Autodesk Fusion 360 part; units mm, degrees
(part 3 of 4)
extrude "Front seam M3x6 clearance (1)" cut sketch "草图15 (4)" along normal blind 3.01 contours A0 in plane through (0, -13, 0) normal (0, 1, 0) bodies 25 in component "12_front_CPU_SUPPORT_FRAME"
ref_plane "工作平面14" through (0, 10, 0) normal (0, 1, 0) x (0, 0, 1) in component "12_front_PCI_SUPPORT_FRAME"
sketch "草图14 (5)" plane through (0, 10, 0) normal (0, 1, 0) x (1, 0, 0) in component "12_front_PCI_SUPPORT_FRAME"
  circle A0 through (148.35, -132, -20) (144.825, -129.9648, -20) (144.825, -134.0352, -20)
extrude "Front seam H4.5 insert (1)" cut sketch "草图14 (5)" along normal blind 6.5 contours A0 in plane through (0, -10, 0) normal (0, 1, 0) bodies 24 in component "12_front_PCI_SUPPORT_FRAME"
ref_plane "工作平面6" through (0, 0, 0) normal (0, 0, 1) x (1, 0, 0) in component "04_front_GROUND_BAR_290mm_FLAT_PSU"
sketch "草图6 (16)" plane through (0, 0, 0) normal (0, 0, 1) x (1, 0, 0) in component "04_front_GROUND_BAR_290mm_FLAT_PSU"
  line L0 (20.45, 29.92) -> (28.45, 29.92)
  line L1 (28.45, 29.92) -> (28.45, 49.92)
  line L2 (28.45, 49.92) -> (20.45, 49.92)
  line L3 (20.45, 49.92) -> (20.45, 29.92)
extrude "PCI bottom lap end seat" add sketch "草图6 (16)" along normal blind 3.2 bodies 18 in component "04_front_GROUND_BAR_290mm_FLAT_PSU"
ref_plane "工作平面7" through (0, 0, 0) normal (0, 0, 1) x (1, 0, 0) in component "04_front_GROUND_BAR_290mm_FLAT_PSU"
sketch "草图7 (14)" plane through (0, 0, 0) normal (0, 0, 1) x (1, 0, 0) in component "04_front_GROUND_BAR_290mm_FLAT_PSU"
  line L0 (286.45, 29.92) -> (294.45, 29.92)
  line L1 (294.45, 29.92) -> (294.45, 49.92)
  line L2 (294.45, 49.92) -> (286.45, 49.92)
  line L3 (286.45, 49.92) -> (286.45, 29.92)
extrude "CPU bottom lap end seat" add sketch "草图7 (14)" along normal blind 3.2 bodies 18 in component "04_front_GROUND_BAR_290mm_FLAT_PSU"
ref_plane "工作平面11" through (0, 0, -0.01) normal (0, 0, 1) x (1, 0, 0) in component "16_PCI_INSET_SIDE_16_45mm"
sketch "草图11 (9)" plane through (0, 0, -0.01) normal (0, 0, 1) x (1, 0, 0) in component "16_PCI_INSET_SIDE_16_45mm"
  line L0 (20.3, 29.77) -> (28.6, 29.77)
  line L1 (28.6, 29.77) -> (28.6, 50.07)
  line L2 (28.6, 50.07) -> (20.3, 50.07)
  line L3 (20.3, 50.07) -> (20.3, 29.77)
extrude "Ground bar seat with lateral print clearance" cut sketch "草图11 (9)" along normal blind 3.21 bodies 27 in component "16_PCI_INSET_SIDE_16_45mm"
ref_plane "工作平面8" through (0, 0, 0) normal (0, 0, 1) x (1, 0, 0) in component "04_front_GROUND_BAR_290mm_FLAT_PSU"
sketch "草图8 (14)" plane through (0, 0, 0) normal (0, 0, 1) x (1, 0, 0) in component "04_front_GROUND_BAR_290mm_FLAT_PSU"
  circle A0 centre (24.45, 39.92) radius 1.7
extrude "Bottom lap M3x6 clearance" cut sketch "草图8 (14)" along normal blind 3.21 bodies 18 in component "04_front_GROUND_BAR_290mm_FLAT_PSU"
ref_plane "工作平面12" through (0, 0, 3.2) normal (0, 0, 1) x (1, 0, 0) in component "16_PCI_INSET_SIDE_16_45mm"
sketch "草图12 (7)" plane through (0, 0, 3.2) normal (0, 0, 1) x (1, 0, 0) in component "16_PCI_INSET_SIDE_16_45mm"
  circle A0 centre (24.45, 39.92) radius 2.35
extrude "Bottom entry H4.5 insert for floor tie" cut sketch "草图12 (7)" along normal blind 6.5 bodies 27 in component "16_PCI_INSET_SIDE_16_45mm"
ref_plane "工作平面9" through (0, 0, -0.01) normal (0, 0, 1) x (1, 0, 0) in component "16_CPU_VERTICAL_SIDE_FLUSH_TO_BEAM"
sketch "草图9 (13)" plane through (0, 0, -0.01) normal (0, 0, 1) x (1, 0, 0) in component "16_CPU_VERTICAL_SIDE_FLUSH_TO_BEAM"
  line L0 (286.3, 29.77) -> (294.6, 29.77)
  line L1 (294.6, 29.77) -> (294.6, 50.07)
  line L2 (294.6, 50.07) -> (286.3, 50.07)
  line L3 (286.3, 50.07) -> (286.3, 29.77)
extrude "Ground bar seat with lateral print clearance'" cut sketch "草图9 (13)" along normal blind 3.21 bodies 26 in component "16_CPU_VERTICAL_SIDE_FLUSH_TO_BEAM"
ref_plane "工作平面9" through (0, 0, 0) normal (0, 0, 1) x (1, 0, 0) in component "04_front_GROUND_BAR_290mm_FLAT_PSU"
sketch "草图9 (14)" plane through (0, 0, 0) normal (0, 0, 1) x (1, 0, 0) in component "04_front_GROUND_BAR_290mm_FLAT_PSU"
  circle A0 centre (290.45, 39.92) radius 1.7
extrude "Bottom lap M3x6 clearance (1)" cut sketch "草图9 (14)" along normal blind 3.21 bodies 18 in component "04_front_GROUND_BAR_290mm_FLAT_PSU"
ref_plane "工作平面10" through (0, 0, 3.2) normal (0, 0, 1) x (1, 0, 0) in component "16_CPU_VERTICAL_SIDE_FLUSH_TO_BEAM"
sketch "草图10 (11)" plane through (0, 0, 3.2) normal (0, 0, 1) x (1, 0, 0) in component "16_CPU_VERTICAL_SIDE_FLUSH_TO_BEAM"
  circle A0 centre (290.45, 39.92) radius 2.35
extrude "Bottom entry H4.5 insert for floor tie'" cut sketch "草图10 (11)" along normal blind 6.5 bodies 26 in component "16_CPU_VERTICAL_SIDE_FLUSH_TO_BEAM"
ref_plane "工作平面17" through (0, 0, 8) normal (0, 0, 1) x (1, 0, 0) in component "05_CENTERED_FLAT_PSU_CRADLE_OPEN_INTAKE"
sketch "草图17" plane through (0, 0, 8) normal (0, 0, 1) x (1, 0, 0) in component "05_CENTERED_FLAT_PSU_CRADLE_OPEN_INTAKE"
  circle A0 centre (79.4, 39.92) radius 1.7
extrude "Cradle to crossbar screw clearance" cut sketch "草图17" along normal blind 22.01 bodies 20 in component "05_CENTERED_FLAT_PSU_CRADLE_OPEN_INTAKE"
ref_plane "工作平面18" through (0, 0, 11) normal (0, 0, 1) x (1, 0, 0) in component "05_CENTERED_FLAT_PSU_CRADLE_OPEN_INTAKE"
sketch "草图18" plane through (0, 0, 11) normal (0, 0, 1) x (1, 0, 0) in component "05_CENTERED_FLAT_PSU_CRADLE_OPEN_INTAKE"
  circle A0 centre (79.4, 39.92) radius 3.3
extrude "Cradle screw well leaving 3 mm web" cut sketch "草图18" along normal blind 19.01 bodies 20 in component "05_CENTERED_FLAT_PSU_CRADLE_OPEN_INTAKE"
ref_plane "工作平面10" through (0, 0, 1.5) normal (0, 0, 1) x (1, 0, 0) in component "04_front_GROUND_BAR_290mm_FLAT_PSU"
sketch "草图10 (12)" plane through (0, 0, 1.5) normal (0, 0, 1) x (1, 0, 0) in component "04_front_GROUND_BAR_290mm_FLAT_PSU"
  circle A0 centre (79.4, 39.92) radius 2.35
extrude "Top entry H4.5 insert for cradle foot" cut sketch "草图10 (12)" along normal blind 6.51 bodies 18 in component "04_front_GROUND_BAR_290mm_FLAT_PSU"
ref_plane "工作平面19" through (0, 0, 8) normal (0, 0, 1) x (1, 0, 0) in component "05_CENTERED_FLAT_PSU_CRADLE_OPEN_INTAKE"
sketch "草图19" plane through (0, 0, 8) normal (0, 0, 1) x (1, 0, 0) in component "05_CENTERED_FLAT_PSU_CRADLE_OPEN_INTAKE"
  circle A0 centre (225.4, 39.92) radius 1.7
extrude "Cradle to crossbar screw clearance (1)" cut sketch "草图19" along normal blind 22.01 bodies 20 in component "05_CENTERED_FLAT_PSU_CRADLE_OPEN_INTAKE"
ref_plane "工作平面20" through (0, 0, 11) normal (0, 0, 1) x (1, 0, 0) in component "05_CENTERED_FLAT_PSU_CRADLE_OPEN_INTAKE"
sketch "草图20" plane through (0, 0, 11) normal (0, 0, 1) x (1, 0, 0) in component "05_CENTERED_FLAT_PSU_CRADLE_OPEN_INTAKE"
  circle A0 centre (225.4, 39.92) radius 3.3
extrude "Cradle screw well leaving 3 mm web (1)" cut sketch "草图20" along normal blind 19.01 bodies 20 in component "05_CENTERED_FLAT_PSU_CRADLE_OPEN_INTAKE"
ref_plane "工作平面11" through (0, 0, 1.5) normal (0, 0, 1) x (1, 0, 0) in component "04_front_GROUND_BAR_290mm_FLAT_PSU"
sketch "草图11 (10)" plane through (0, 0, 1.5) normal (0, 0, 1) x (1, 0, 0) in component "04_front_GROUND_BAR_290mm_FLAT_PSU"
  circle A0 centre (225.4, 39.92) radius 2.35
extrude "Top entry H4.5 insert for cradle foot (1)" cut sketch "草图11 (10)" along normal blind 6.51 bodies 18 in component "04_front_GROUND_BAR_290mm_FLAT_PSU"
ref_plane "工作平面6" through (0, 0, 0) normal (0, 0, 1) x (1, 0, 0) in component "04_rear_GROUND_BAR_290mm_FLAT_PSU"
sketch "草图6 (17)" plane through (0, 0, 0) normal (0, 0, 1) x (1, 0, 0) in component "04_rear_GROUND_BAR_290mm_FLAT_PSU"
  line L0 (20.45, 193.92) -> (28.45, 193.92)
  line L1 (28.45, 193.92) -> (28.45, 213.92)
  line L2 (28.45, 213.92) -> (20.45, 213.92)
  line L3 (20.45, 213.92) -> (20.45, 193.92)
extrude "PCI bottom lap end seat'" add sketch "草图6 (17)" along normal blind 3.2 bodies 19 in component "04_rear_GROUND_BAR_290mm_FLAT_PSU"
ref_plane "工作平面7" through (0, 0, 0) normal (0, 0, 1) x (1, 0, 0) in component "04_rear_GROUND_BAR_290mm_FLAT_PSU"
sketch "草图7 (15)" plane through (0, 0, 0) normal (0, 0, 1) x (1, 0, 0) in component "04_rear_GROUND_BAR_290mm_FLAT_PSU"
  line L0 (286.45, 193.92) -> (294.45, 193.92)
  line L1 (294.45, 193.92) -> (294.45, 213.92)
  line L2 (294.45, 213.92) -> (286.45, 213.92)
  line L3 (286.45, 213.92) -> (286.45, 193.92)
extrude "CPU bottom lap end seat'" add sketch "草图7 (15)" along normal blind 3.2 bodies 19 in component "04_rear_GROUND_BAR_290mm_FLAT_PSU"
ref_plane "工作平面13" through (0, 0, -0.01) normal (0, 0, 1) x (1, 0, 0) in component "16_PCI_INSET_SIDE_16_45mm"
sketch "草图13 (7)" plane through (0, 0, -0.01) normal (0, 0, 1) x (1, 0, 0) in component "16_PCI_INSET_SIDE_16_45mm"
  line L0 (20.3, 193.77) -> (28.6, 193.77)
  line L1 (28.6, 193.77) -> (28.6, 214.07)
  line L2 (28.6, 214.07) -> (20.3, 214.07)
  line L3 (20.3, 214.07) -> (20.3, 193.77)
extrude "Ground bar seat with lateral print clearance (1)" cut sketch "草图13 (7)" along normal blind 3.21 bodies 27 in component "16_PCI_INSET_SIDE_16_45mm"
ref_plane "工作平面8" through (0, 0, 0) normal (0, 0, 1) x (1, 0, 0) in component "04_rear_GROUND_BAR_290mm_FLAT_PSU"
sketch "草图8 (15)" plane through (0, 0, 0) normal (0, 0, 1) x (1, 0, 0) in component "04_rear_GROUND_BAR_290mm_FLAT_PSU"
  circle A0 centre (24.45, 203.92) radius 1.7
extrude "Bottom lap M3x6 clearance'" cut sketch "草图8 (15)" along normal blind 3.21 bodies 19 in component "04_rear_GROUND_BAR_290mm_FLAT_PSU"
ref_plane "工作平面14" through (0, 0, 3.2) normal (0, 0, 1) x (1, 0, 0) in component "16_PCI_INSET_SIDE_16_45mm"
sketch "草图14 (6)" plane through (0, 0, 3.2) normal (0, 0, 1) x (1, 0, 0) in component "16_PCI_INSET_SIDE_16_45mm"
  circle A0 centre (24.45, 203.92) radius 2.35
extrude "Bottom entry H4.5 insert for floor tie (1)" cut sketch "草图14 (6)" along normal blind 6.5 bodies 27 in component "16_PCI_INSET_SIDE_16_45mm"
ref_plane "工作平面11" through (0, 0, -0.01) normal (0, 0, 1) x (1, 0, 0) in component "16_CPU_VERTICAL_SIDE_FLUSH_TO_BEAM"
sketch "草图11 (11)" plane through (0, 0, -0.01) normal (0, 0, 1) x (1, 0, 0) in component "16_CPU_VERTICAL_SIDE_FLUSH_TO_BEAM"
  line L0 (286.3, 193.77) -> (294.6, 193.77)
  line L1 (294.6, 193.77) -> (294.6, 214.07)
  line L2 (294.6, 214.07) -> (286.3, 214.07)
  line L3 (286.3, 214.07) -> (286.3, 193.77)
extrude "Ground bar seat with lateral print clearance (1)'" cut sketch "草图11 (11)" along normal blind 3.21 bodies 26 in component "16_CPU_VERTICAL_SIDE_FLUSH_TO_BEAM"
ref_plane "工作平面9" through (0, 0, 0) normal (0, 0, 1) x (1, 0, 0) in component "04_rear_GROUND_BAR_290mm_FLAT_PSU"
sketch "草图9 (15)" plane through (0, 0, 0) normal (0, 0, 1) x (1, 0, 0) in component "04_rear_GROUND_BAR_290mm_FLAT_PSU"
  circle A0 centre (290.45, 203.92) radius 1.7
extrude "Bottom lap M3x6 clearance (1)'" cut sketch "草图9 (15)" along normal blind 3.21 bodies 19 in component "04_rear_GROUND_BAR_290mm_FLAT_PSU"
ref_plane "工作平面12" through (0, 0, 3.2) normal (0, 0, 1) x (1, 0, 0) in component "16_CPU_VERTICAL_SIDE_FLUSH_TO_BEAM"
sketch "草图12 (8)" plane through (0, 0, 3.2) normal (0, 0, 1) x (1, 0, 0) in component "16_CPU_VERTICAL_SIDE_FLUSH_TO_BEAM"
  circle A0 centre (290.45, 203.92) radius 2.35
extrude "Bottom entry H4.5 insert for floor tie (1)'" cut sketch "草图12 (8)" along normal blind 6.5 bodies 26 in component "16_CPU_VERTICAL_SIDE_FLUSH_TO_BEAM"
ref_plane "工作平面21" through (0, 0, 8) normal (0, 0, 1) x (1, 0, 0) in component "05_CENTERED_FLAT_PSU_CRADLE_OPEN_INTAKE"
sketch "草图21" plane through (0, 0, 8) normal (0, 0, 1) x (1, 0, 0) in component "05_CENTERED_FLAT_PSU_CRADLE_OPEN_INTAKE"
  circle A0 centre (79.4, 203.92) radius 1.7
extrude "Cradle to crossbar screw clearance (2)" cut sketch "草图21" along normal blind 22.01 bodies 20 in component "05_CENTERED_FLAT_PSU_CRADLE_OPEN_INTAKE"
ref_plane "工作平面22" through (0, 0, 11) normal (0, 0, 1) x (1, 0, 0) in component "05_CENTERED_FLAT_PSU_CRADLE_OPEN_INTAKE"
sketch "草图22" plane through (0, 0, 11) normal (0, 0, 1) x (1, 0, 0) in component "05_CENTERED_FLAT_PSU_CRADLE_OPEN_INTAKE"
  circle A0 centre (79.4, 203.92) radius 3.3
extrude "Cradle screw well leaving 3 mm web (2)" cut sketch "草图22" along normal blind 19.01 bodies 20 in component "05_CENTERED_FLAT_PSU_CRADLE_OPEN_INTAKE"
ref_plane "工作平面10" through (0, 0, 1.5) normal (0, 0, 1) x (1, 0, 0) in component "04_rear_GROUND_BAR_290mm_FLAT_PSU"
sketch "草图10 (13)" plane through (0, 0, 1.5) normal (0, 0, 1) x (1, 0, 0) in component "04_rear_GROUND_BAR_290mm_FLAT_PSU"
  circle A0 centre (79.4, 203.92) radius 2.35
extrude "Top entry H4.5 insert for cradle foot'" cut sketch "草图10 (13)" along normal blind 6.51 bodies 19 in component "04_rear_GROUND_BAR_290mm_FLAT_PSU"
ref_plane "工作平面23" through (0, 0, 8) normal (0, 0, 1) x (1, 0, 0) in component "05_CENTERED_FLAT_PSU_CRADLE_OPEN_INTAKE"
sketch "草图23" plane through (0, 0, 8) normal (0, 0, 1) x (1, 0, 0) in component "05_CENTERED_FLAT_PSU_CRADLE_OPEN_INTAKE"
  circle A0 centre (225.4, 203.92) radius 1.7
extrude "Cradle to crossbar screw clearance (3)" cut sketch "草图23" along normal blind 22.01 bodies 20 in component "05_CENTERED_FLAT_PSU_CRADLE_OPEN_INTAKE"
ref_plane "工作平面24" through (0, 0, 11) normal (0, 0, 1) x (1, 0, 0) in component "05_CENTERED_FLAT_PSU_CRADLE_OPEN_INTAKE"
sketch "草图24" plane through (0, 0, 11) normal (0, 0, 1) x (1, 0, 0) in component "05_CENTERED_FLAT_PSU_CRADLE_OPEN_INTAKE"
  circle A0 centre (225.4, 203.92) radius 3.3
extrude "Cradle screw well leaving 3 mm web (3)" cut sketch "草图24" along normal blind 19.01 bodies 20 in component "05_CENTERED_FLAT_PSU_CRADLE_OPEN_INTAKE"
ref_plane "工作平面11" through (0, 0, 1.5) normal (0, 0, 1) x (1, 0, 0) in component "04_rear_GROUND_BAR_290mm_FLAT_PSU"
sketch "草图11 (12)" plane through (0, 0, 1.5) normal (0, 0, 1) x (1, 0, 0) in component "04_rear_GROUND_BAR_290mm_FLAT_PSU"
  circle A0 centre (225.4, 203.92) radius 2.35
extrude "Top entry H4.5 insert for cradle foot (1)'" cut sketch "草图11 (12)" along normal blind 6.51 bodies 19 in component "04_rear_GROUND_BAR_290mm_FLAT_PSU"
ref_plane "工作平面25" through (0, 0, 23.99) normal (0, 0, 1) x (1, 0, 0) in component "05_CENTERED_FLAT_PSU_CRADLE_OPEN_INTAKE"
sketch "草图25" plane through (0, 0, 23.99) normal (0, 0, 1) x (1, 0, 0) in component "05_CENTERED_FLAT_PSU_CRADLE_OPEN_INTAKE"
  line L0 (87.1, 35) -> (90.7, 35)
  line L1 (90.7, 35) -> (90.7, 37.4)
  line L2 (90.7, 37.4) -> (87.1, 37.4)
  line L3 (87.1, 37.4) -> (87.1, 35)
extrude "3 mm strap slot outside PSU fan intake" cut sketch "草图25" along normal blind 6.02 bodies 20 in component "05_CENTERED_FLAT_PSU_CRADLE_OPEN_INTAKE"
ref_plane "工作平面26" through (0, 0, 23.99) normal (0, 0, 1) x (1, 0, 0) in component "05_CENTERED_FLAT_PSU_CRADLE_OPEN_INTAKE"
sketch "草图26" plane through (0, 0, 23.99) normal (0, 0, 1) x (1, 0, 0) in component "05_CENTERED_FLAT_PSU_CRADLE_OPEN_INTAKE"
  line L0 (87.1, 206.2) -> (90.7, 206.2)
  line L1 (90.7, 206.2) -> (90.7, 208.6)
  line L2 (90.7, 208.6) -> (87.1, 208.6)
  line L3 (87.1, 208.6) -> (87.1, 206.2)
extrude "3 mm strap slot outside PSU fan intake (1)" cut sketch "草图26" along normal blind 6.02 bodies 20 in component "05_CENTERED_FLAT_PSU_CRADLE_OPEN_INTAKE"
ref_plane "工作平面27" through (0, 0, 23.99) normal (0, 0, 1) x (1, 0, 0) in component "05_CENTERED_FLAT_PSU_CRADLE_OPEN_INTAKE"
sketch "草图27" plane through (0, 0, 23.99) normal (0, 0, 1) x (1, 0, 0) in component "05_CENTERED_FLAT_PSU_CRADLE_OPEN_INTAKE"
  line L0 (214.1, 35) -> (217.7, 35)
  line L1 (217.7, 35) -> (217.7, 37.4)
  line L2 (217.7, 37.4) -> (214.1, 37.4)
  line L3 (214.1, 37.4) -> (214.1, 35)
extrude "3 mm strap slot outside PSU fan intake (2)" cut sketch "草图27" along normal blind 6.02 bodies 20 in component "05_CENTERED_FLAT_PSU_CRADLE_OPEN_INTAKE"
ref_plane "工作平面28" through (0, 0, 23.99) normal (0, 0, 1) x (1, 0, 0) in component "05_CENTERED_FLAT_PSU_CRADLE_OPEN_INTAKE"
sketch "草图28" plane through (0, 0, 23.99) normal (0, 0, 1) x (1, 0, 0) in component "05_CENTERED_FLAT_PSU_CRADLE_OPEN_INTAKE"
  line L0 (214.1, 206.2) -> (217.7, 206.2)
  line L1 (217.7, 206.2) -> (217.7, 208.6)
  line L2 (217.7, 208.6) -> (214.1, 208.6)
  line L3 (214.1, 208.6) -> (214.1, 206.2)
extrude "3 mm strap slot outside PSU fan intake (3)" cut sketch "草图28" along normal blind 6.02 bodies 20 in component "05_CENTERED_FLAT_PSU_CRADLE_OPEN_INTAKE"
ref_plane "工作平面7" through (0, 0, 210) normal (0, 0, 1) x (1, 0, 0) in component "10_GPU_140_FAN_MOUNT"
sketch "草图7 (16)" plane through (0, 0, 210) normal (0, 0, 1) x (1, 0, 0) in component "10_GPU_140_FAN_MOUNT"
  line L0 (26.4, -19) -> (38.4, -19)
  line L1 (38.4, -19) -> (38.4, -9)
  line L2 (38.4, -9) -> (26.4, -9)
  line L3 (26.4, -9) -> (26.4, -19)
extrude "Integral 3 mm fan panel fastening tab" add sketch "草图7 (16)" along normal blind 3 bodies 1 in component "10_GPU_140_FAN_MOUNT"
ref_plane "工作平面8" through (0, 0, 210) normal (0, 0, 1) x (1, 0, 0) in component "10_GPU_140_FAN_MOUNT"
sketch "草图8 (16)" plane through (0, 0, 210) normal (0, 0, 1) x (1, 0, 0) in component "10_GPU_140_FAN_MOUNT"
  circle A0 centre (32.4, -14) radius 1.7
extrude "M3x6 fan panel tab clearance" cut sketch "草图8 (16)" along normal blind 3.01 bodies 1 in component "10_GPU_140_FAN_MOUNT"
ref_plane "工作平面14" through (0, 0, 148) normal (0, 0, 1) x (1, 0, 0) in component "20_ONE_PIECE_DUAL_140_FAN_RAIL_284mm"
sketch "草图14 (7)" plane through (0, 0, 148) normal (0, 0, 1) x (1, 0, 0) in component "20_ONE_PIECE_DUAL_140_FAN_RAIL_284mm"
  line L0 (26.4, -19) -> (38.4, -19)
  line L1 (38.4, -19) -> (38.4, -9)
  line L2 (38.4, -9) -> (26.4, -9)
  line L3 (26.4, -9) -> (26.4, -19)
extrude "Integral fan panel tab support pad" add sketch "草图14 (7)" along normal blind 12 bodies 32 in component "20_ONE_PIECE_DUAL_140_FAN_RAIL_284mm"
ref_plane "工作平面15" through (0, 0, 153.5) normal (0, 0, 1) x (1, 0, 0) in component "20_ONE_PIECE_DUAL_140_FAN_RAIL_284mm"
sketch "草图15 (5)" plane through (0, 0, 153.5) normal (0, 0, 1) x (1, 0, 0) in component "20_ONE_PIECE_DUAL_140_FAN_RAIL_284mm"
  circle A0 centre (32.4, -14) radius 2.35
extrude "H4.5 insert for fan panel M3x6 fastening" cut sketch "草图15 (5)" along normal blind 6.51 bodies 32 in component "20_ONE_PIECE_DUAL_140_FAN_RAIL_284mm"
ref_plane "工作平面9" through (0, 0, 210) normal (0, 0, 1) x (1, 0, 0) in component "10_GPU_140_FAN_MOUNT"
sketch "草图9 (16)" plane through (0, 0, 210) normal (0, 0, 1) x (1, 0, 0) in component "10_GPU_140_FAN_MOUNT"
  line L0 (126.4, -19) -> (138.4, -19)
  line L1 (138.4, -19) -> (138.4, -9)
  line L2 (138.4, -9) -> (126.4, -9)
  line L3 (126.4, -9) -> (126.4, -19)
extrude "Integral 3 mm fan panel fastening tab (1)" add sketch "草图9 (16)" along normal blind 3 bodies 1 in component "10_GPU_140_FAN_MOUNT"
ref_plane "工作平面10" through (0, 0, 210) normal (0, 0, 1) x (1, 0, 0) in component "10_GPU_140_FAN_MOUNT"
sketch "草图10 (14)" plane through (0, 0, 210) normal (0, 0, 1) x (1, 0, 0) in component "10_GPU_140_FAN_MOUNT"
  circle A0 centre (132.4, -14) radius 1.7
extrude "M3x6 fan panel tab clearance (1)" cut sketch "草图10 (14)" along normal blind 3.01 bodies 1 in component "10_GPU_140_FAN_MOUNT"
ref_plane "工作平面16" through (0, 0, 148) normal (0, 0, 1) x (1, 0, 0) in component "20_ONE_PIECE_DUAL_140_FAN_RAIL_284mm"
sketch "草图16 (4)" plane through (0, 0, 148) normal (0, 0, 1) x (1, 0, 0) in component "20_ONE_PIECE_DUAL_140_FAN_RAIL_284mm"
  line L0 (126.4, -19) -> (138.4, -19)
  line L1 (138.4, -19) -> (138.4, -9)
  line L2 (138.4, -9) -> (126.4, -9)
  line L3 (126.4, -9) -> (126.4, -19)
extrude "Integral fan panel tab support pad (1)" add sketch "草图16 (4)" along normal blind 12 bodies 32 in component "20_ONE_PIECE_DUAL_140_FAN_RAIL_284mm"
ref_plane "工作平面17" through (0, 0, 153.5) normal (0, 0, 1) x (1, 0, 0) in component "20_ONE_PIECE_DUAL_140_FAN_RAIL_284mm"
sketch "草图17 (2)" plane through (0, 0, 153.5) normal (0, 0, 1) x (1, 0, 0) in component "20_ONE_PIECE_DUAL_140_FAN_RAIL_284mm"
  circle A0 centre (132.4, -14) radius 2.35
extrude "H4.5 insert for fan panel M3x6 fastening (1)" cut sketch "草图17 (2)" along normal blind 6.51 bodies 32 in component "20_ONE_PIECE_DUAL_140_FAN_RAIL_284mm"
ref_plane "工作平面7" through (0, 0, 210) normal (0, 0, 1) x (1, 0, 0) in component "10_CPU_140_FAN_MOUNT"
sketch "草图7 (17)" plane through (0, 0, 210) normal (0, 0, 1) x (1, 0, 0) in component "10_CPU_140_FAN_MOUNT"
  line L0 (170.4, -19) -> (182.4, -19)
  line L1 (182.4, -19) -> (182.4, -9)
  line L2 (182.4, -9) -> (170.4, -9)
  line L3 (170.4, -9) -> (170.4, -19)
extrude "Integral 3 mm fan panel fastening tab'" add sketch "草图7 (17)" along normal blind 3 bodies 2 in component "10_CPU_140_FAN_MOUNT"
ref_plane "工作平面8" through (0, 0, 210) normal (0, 0, 1) x (1, 0, 0) in component "10_CPU_140_FAN_MOUNT"
sketch "草图8 (17)" plane through (0, 0, 210) normal (0, 0, 1) x (1, 0, 0) in component "10_CPU_140_FAN_MOUNT"
  circle A0 centre (176.4, -14) radius 1.7
extrude "M3x6 fan panel tab clearance'" cut sketch "草图8 (17)" along normal blind 3.01 bodies 2 in component "10_CPU_140_FAN_MOUNT"
ref_plane "工作平面18" through (0, 0, 148) normal (0, 0, 1) x (1, 0, 0) in component "20_ONE_PIECE_DUAL_140_FAN_RAIL_284mm"
sketch "草图18 (2)" plane through (0, 0, 148) normal (0, 0, 1) x (1, 0, 0) in component "20_ONE_PIECE_DUAL_140_FAN_RAIL_284mm"
  line L0 (170.4, -19) -> (182.4, -19)
  line L1 (182.4, -19) -> (182.4, -9)
  line L2 (182.4, -9) -> (170.4, -9)
  line L3 (170.4, -9) -> (170.4, -19)
extrude "Integral fan panel tab support pad (2)" add sketch "草图18 (2)" along normal blind 12 bodies 32 in component "20_ONE_PIECE_DUAL_140_FAN_RAIL_284mm"
ref_plane "工作平面19" through (0, 0, 153.5) normal (0, 0, 1) x (1, 0, 0) in component "20_ONE_PIECE_DUAL_140_FAN_RAIL_284mm"
sketch "草图19 (2)" plane through (0, 0, 153.5) normal (0, 0, 1) x (1, 0, 0) in component "20_ONE_PIECE_DUAL_140_FAN_RAIL_284mm"
  circle A0 centre (176.4, -14) radius 2.35
extrude "H4.5 insert for fan panel M3x6 fastening (2)" cut sketch "草图19 (2)" along normal blind 6.51 bodies 32 in component "20_ONE_PIECE_DUAL_140_FAN_RAIL_284mm"
ref_plane "工作平面9" through (0, 0, 210) normal (0, 0, 1) x (1, 0, 0) in component "10_CPU_140_FAN_MOUNT"
sketch "草图9 (17)" plane through (0, 0, 210) normal (0, 0, 1) x (1, 0, 0) in component "10_CPU_140_FAN_MOUNT"
  line L0 (270.4, -19) -> (282.4, -19)
  line L1 (282.4, -19) -> (282.4, -9)
  line L2 (282.4, -9) -> (270.4, -9)
  line L3 (270.4, -9) -> (270.4, -19)
extrude "Integral 3 mm fan panel fastening tab (1)'" add sketch "草图9 (17)" along normal blind 3 bodies 2 in component "10_CPU_140_FAN_MOUNT"
ref_plane "工作平面10" through (0, 0, 210) normal (0, 0, 1) x (1, 0, 0) in component "10_CPU_140_FAN_MOUNT"
sketch "草图10 (15)" plane through (0, 0, 210) normal (0, 0, 1) x (1, 0, 0) in component "10_CPU_140_FAN_MOUNT"
  circle A0 centre (276.4, -14) radius 1.7
extrude "M3x6 fan panel tab clearance (1)'" cut sketch "草图10 (15)" along normal blind 3.01 bodies 2 in component "10_CPU_140_FAN_MOUNT"
ref_plane "工作平面20" through (0, 0, 148) normal (0, 0, 1) x (1, 0, 0) in component "20_ONE_PIECE_DUAL_140_FAN_RAIL_284mm"
sketch "草图20 (2)" plane through (0, 0, 148) normal (0, 0, 1) x (1, 0, 0) in component "20_ONE_PIECE_DUAL_140_FAN_RAIL_284mm"
  line L0 (270.4, -19) -> (282.4, -19)
  line L1 (282.4, -19) -> (282.4, -9)
  line L2 (282.4, -9) -> (270.4, -9)
  line L3 (270.4, -9) -> (270.4, -19)
extrude "Integral fan panel tab support pad (3)" add sketch "草图20 (2)" along normal blind 12 bodies 32 in component "20_ONE_PIECE_DUAL_140_FAN_RAIL_284mm"
ref_plane "工作平面21" through (0, 0, 153.5) normal (0, 0, 1) x (1, 0, 0) in component "20_ONE_PIECE_DUAL_140_FAN_RAIL_284mm"
sketch "草图21 (2)" plane through (0, 0, 153.5) normal (0, 0, 1) x (1, 0, 0) in component "20_ONE_PIECE_DUAL_140_FAN_RAIL_284mm"
  circle A0 centre (276.4, -14) radius 2.35
extrude "H4.5 insert for fan panel M3x6 fastening (3)" cut sketch "草图21 (2)" along normal blind 6.51 bodies 32 in component "20_ONE_PIECE_DUAL_140_FAN_RAIL_284mm"
ref_plane "工作平面17" through (0, 0, 119.9) normal (0, 0, 1) x (1, 0, 0) in component "18_ONE_PIECE_REAR_LOAD_BEAM_304_45mm"
sketch "草图17 (3)" plane through (0, 0, 119.9) normal (0, 0, 1) x (1, 0, 0) in component "18_ONE_PIECE_REAR_LOAD_BEAM_304_45mm"
  line L0 (87, 246.3) -> (125, 246.3)
  line L1 (125, 246.3) -> (125, 248.7)
  line L2 (125, 248.7) -> (87, 248.7)
  line L3 (87, 248.7) -> (87, 246.3)
extrude "V18 join both tab slots and widen each outer end by 2 mm" cut sketch "草图17 (3)" along normal blind 20.2 bodies 31 in component "18_ONE_PIECE_REAR_LOAD_BEAM_304_45mm"
ref_plane "工作平面1" through (0, -264, 0) normal (0, 1, 0) x (0, 0, 1) in component "07_GPU_INTEGRATED_LIGHTWEIGHT_FRAME"
sketch "草图1 (29)" plane through (0, -264, 0) normal (0, 1, 0) x (1, 0, 0) in component "07_GPU_INTEGRATED_LIGHTWEIGHT_FRAME"
  line L0 (76, -140, 528) -> (144, -140, 528)
  arc A0 through (150, -146, 528) (148.2426, -141.7574, 528) (144, -140, 528)
  line L1 (150, -146, 528) -> (150, -262, 528)
  arc A1 through (144, -268, 528) (148.2426, -266.2426, 528) (150, -262, 528)
  line L2 (144, -268, 528) -> (76, -268, 528)
  arc A2 through (70, -262, 528) (71.7574, -266.2426, 528) (76, -268, 528)
  line L3 (70, -262, 528) -> (70, -146, 528)
  arc A3 through (76, -140, 528) (71.7574, -141.7574, 528) (70, -146, 528)
extrude "V20 continuous rounded structural perimeter 8 mm web" add sketch "草图1 (29)" along normal blind 8 separate body contours L0 A0 L1 A1 L2 A2 L3 A3 in plane through (0, 264, 0) normal (0, 1, 0) makes body 33 in component "07_GPU_INTEGRATED_LIGHTWEIGHT_FRAME"
ref_plane "工作平面2" through (0, -263.99, 0) normal (0, 1, 0) x (0, 0, 1) in component "07_GPU_INTEGRATED_LIGHTWEIGHT_FRAME"
sketch "草图2 (20)" plane through (0, -263.99, 0) normal (0, 1, 0) x (1, 0, 0) in component "07_GPU_INTEGRATED_LIGHTWEIGHT_FRAME"
  line L0 (92, -162, 527.98) -> (128, -162, 527.98)
  arc A0 through (134, -168, 527.98) (132.2426, -163.7574, 527.98) (128, -162, 527.98)
  line L1 (134, -168, 527.98) -> (134, -244, 527.98)
  arc A1 through (128, -250, 527.98) (132.2426, -248.2426, 527.98) (134, -244, 527.98)
  line L2 (128, -250, 527.98) -> (92, -250, 527.98)
  arc A2 through (86, -244, 527.98) (87.7574, -248.2426, 527.98) (92, -250, 527.98)
  line L3 (86, -244, 527.98) -> (86, -168, 527.98)
  arc A3 through (92, -162, 527.98) (87.7574, -163.7574, 527.98) (86, -168, 527.98)
extrude "V20 enlarged R6 window retaining V19 protected port clearance" cut sketch "草图2 (20)" along normal blind 8.02 contours L0 A0 L1 A1 L2 A2 L3 A3 in plane through (0, 263.99, 0) normal (0, 1, 0) bodies 33 in component "07_GPU_INTEGRATED_LIGHTWEIGHT_FRAME"
ref_plane "工作平面3" through (0, 0, 140) normal (0, 0, 1) x (1, 0, 0) in component "07_GPU_INTEGRATED_LIGHTWEIGHT_FRAME"
sketch "草图3 (19)" plane through (0, 0, 140) normal (0, 0, 1) x (1, 0, 0) in component "07_GPU_INTEGRATED_LIGHTWEIGHT_FRAME"
  line L0 (73, 244) -> (147, 244)
  arc A0 (147, 244) -> (150, 247) centre (147, 247) ccw
  line L1 (150, 247) -> (150, 269)
  arc A1 (150, 269) -> (147, 272) centre (147, 269) ccw
  line L2 (147, 272) -> (73, 272)
  arc A2 (73, 272) -> (70, 269) centre (73, 269) ccw
  line L3 (70, 269) -> (70, 247)
  arc A3 (70, 247) -> (73, 244) centre (73, 247) ccw
extrude "V20 integral rounded 8 mm mounting sole" add sketch "草图3 (19)" along normal blind 8 bodies 33 in component "07_GPU_INTEGRATED_LIGHTWEIGHT_FRAME"
ref_plane "工作平面4" through (84, 0, 0) normal (1, 0, 0) x (0, 1, 0) in component "07_GPU_INTEGRATED_LIGHTWEIGHT_FRAME"
sketch "草图4 (19)" plane through (84, 0, 0) normal (1, 0, 0) x (0, 0, -1) in component "07_GPU_INTEGRATED_LIGHTWEIGHT_FRAME"
  line L0 (-258, 246.84) -> (-250, 264)
  line L1 (-250, 264) -> (-268, 264)
  line L2 (-268, 264) -> (-268, 246.84)
  line L3 (-268, 246.84) -> (-258, 246.84)
extrude "V20 integral tapered ear ledge root no separate clamp backplate" add sketch "草图4 (19)" along normal blind 46 bodies 33 in component "07_GPU_INTEGRATED_LIGHTWEIGHT_FRAME"
ref_plane "工作平面5" through (85, 0, 0) normal (1, 0, 0) x (0, 1, 0) in component "07_GPU_INTEGRATED_LIGHTWEIGHT_FRAME"
sketch "草图5 (18)" plane through (85, 0, 0) normal (1, 0, 0) x (0, 0, -1) in component "07_GPU_INTEGRATED_LIGHTWEIGHT_FRAME"
  line L0 (-148, 244.84) -> (-148, 264)
  line L1 (-148, 264) -> (-162, 264)
  line L2 (-162, 264) -> (-158, 254)
  line L3 (-158, 254) -> (-158, 244.84)
  line L4 (-158, 244.84) -> (-148, 244.84)
extrude "V20 integral tab guide blended into lower structural sill" add sketch "草图5 (18)" along normal blind 47 bodies 33 in component "07_GPU_INTEGRATED_LIGHTWEIGHT_FRAME"
ref_plane "工作平面6" through (70, 0, 0) normal (1, 0, 0) x (0, 1, 0) in component "07_GPU_INTEGRATED_LIGHTWEIGHT_FRAME"
sketch "草图6 (18)" plane through (70, 0, 0) normal (1, 0, 0) x (0, 0, -1) in component "07_GPU_INTEGRATED_LIGHTWEIGHT_FRAME"
  line L0 (-148, 254) -> (-148, 264)
  line L1 (-148, 264) -> (-218, 264)
  arc A0 (-218, 264) -> (-148, 254) centre (-149.4122, 494.1149) ccw
extrude "V20 continuous curved base to upright rib" add sketch "草图6 (18)" along normal blind 10 bodies 33 in component "07_GPU_INTEGRATED_LIGHTWEIGHT_FRAME"
ref_plane "工作平面7" through (140, 0, 0) normal (1, 0, 0) x (0, 1, 0) in component "07_GPU_INTEGRATED_LIGHTWEIGHT_FRAME"
sketch "草图7 (18)" plane through (140, 0, 0) normal (1, 0, 0) x (0, 0, -1) in component "07_GPU_INTEGRATED_LIGHTWEIGHT_FRAME"
  line L0 (-148, 254) -> (-148, 264)
  line L1 (-148, 264) -> (-218, 264)
  arc A0 (-218, 264) -> (-148, 254) centre (-149.4122, 494.1149) ccw
extrude "V20 continuous curved base to upright rib (1)" add sketch "草图7 (18)" along normal blind 10 bodies 33 in component "07_GPU_INTEGRATED_LIGHTWEIGHT_FRAME"
fillet "V20 rounded upper ledge forward corners" radius 1.5 2 edges at (84, 246.84, 263) (130, 246.84, 263) on bodies 33 in component "07_GPU_INTEGRATED_LIGHTWEIGHT_FRAME"
fillet "V20 R2 rib to upright root transitions" radius 2 2 edges at (140, 264, 183) (80, 264, 183) on bodies 33 in component "07_GPU_INTEGRATED_LIGHTWEIGHT_FRAME"
ref_plane "工作平面8" through (0, 0, 139.99) normal (0, 0, 1) x (1, 0, 0) in component "07_GPU_INTEGRATED_LIGHTWEIGHT_FRAME"
sketch "草图8 (18)" plane through (0, 0, 139.99) normal (0, 0, 1) x (1, 0, 0) in component "07_GPU_INTEGRATED_LIGHTWEIGHT_FRAME"
  line L0 (87, 246.3) -> (125, 246.3)
  line L1 (125, 246.3) -> (125, 248.7)
  line L2 (125, 248.7) -> (87, 248.7)
  line L3 (87, 248.7) -> (87, 246.3)
extrude "V20 retain full V18 V19 continuous tab passage" cut sketch "草图8 (18)" along normal blind 18.11 bodies 33 in component "07_GPU_INTEGRATED_LIGHTWEIGHT_FRAME"
ref_plane "工作平面9" through (0, 0, 140) normal (0, 0, 1) x (1, 0, 0) in component "07_GPU_INTEGRATED_LIGHTWEIGHT_FRAME"
sketch "草图9 (18)" plane through (0, 0, 140) normal (0, 0, 1) x (1, 0, 0) in component "07_GPU_INTEGRATED_LIGHTWEIGHT_FRAME"
  circle A0 centre (80, 248.5) radius 1.7
extrude "V20 unchanged base M3 clearance" cut sketch "草图9 (18)" along normal blind 8 bodies 33 in component "07_GPU_INTEGRATED_LIGHTWEIGHT_FRAME"
ref_plane "工作平面10" through (0, 0, 143) normal (0, 0, 1) x (1, 0, 0) in component "07_GPU_INTEGRATED_LIGHTWEIGHT_FRAME"
sketch "草图10 (16)" plane through (0, 0, 143) normal (0, 0, 1) x (1, 0, 0) in component "07_GPU_INTEGRATED_LIGHTWEIGHT_FRAME"
  circle A0 centre (80, 248.5) radius 4.1
extrude "V20 unchanged head well and 3 mm bearing web" cut sketch "草图10 (16)" along normal blind 5.01 bodies 33 in component "07_GPU_INTEGRATED_LIGHTWEIGHT_FRAME"
ref_plane "工作平面11" through (0, 0, 148.001) normal (0, 0, 1) x (1, 0, 0) in component "07_GPU_INTEGRATED_LIGHTWEIGHT_FRAME"
sketch "草图11 (13)" plane through (0, 0, 148.001) normal (0, 0, 1) x (1, 0, 0) in component "07_GPU_INTEGRATED_LIGHTWEIGHT_FRAME"
  circle A0 centre (80, 248.5) radius 5.3
extrude "V20 full height driver access through permanent ledges" cut sketch "草图11 (13)" along normal blind 120.1 bodies 33 in component "07_GPU_INTEGRATED_LIGHTWEIGHT_FRAME"
ref_plane "工作平面12" through (0, 0, 140) normal (0, 0, 1) x (1, 0, 0) in component "07_GPU_INTEGRATED_LIGHTWEIGHT_FRAME"
sketch "草图12 (9)" plane through (0, 0, 140) normal (0, 0, 1) x (1, 0, 0) in component "07_GPU_INTEGRATED_LIGHTWEIGHT_FRAME"
  circle A0 centre (140, 248.5) radius 1.7
extrude "V20 unchanged base M3 clearance (1)" cut sketch "草图12 (9)" along normal blind 8 bodies 33 in component "07_GPU_INTEGRATED_LIGHTWEIGHT_FRAME"
ref_plane "工作平面13" through (0, 0, 143) normal (0, 0, 1) x (1, 0, 0) in component "07_GPU_INTEGRATED_LIGHTWEIGHT_FRAME"
sketch "草图13 (8)" plane through (0, 0, 143) normal (0, 0, 1) x (1, 0, 0) in component "07_GPU_INTEGRATED_LIGHTWEIGHT_FRAME"
  circle A0 centre (140, 248.5) radius 4.1
extrude "V20 unchanged head well and 3 mm bearing web (1)" cut sketch "草图13 (8)" along normal blind 5.01 bodies 33 in component "07_GPU_INTEGRATED_LIGHTWEIGHT_FRAME"
ref_plane "工作平面14" through (0, 0, 261.5) normal (0, 0, 1) x (1, 0, 0) in component "07_GPU_INTEGRATED_LIGHTWEIGHT_FRAME"
sketch "草图14 (8)" plane through (0, 0, 261.5) normal (0, 0, 1) x (1, 0, 0) in component "07_GPU_INTEGRATED_LIGHTWEIGHT_FRAME"
  circle A0 centre (100, 251) radius 2.35
extrude "V20 unchanged upper ear short M3 heat insert" cut sketch "草图14 (8)" along normal blind 6.5 bodies 33 in component "07_GPU_INTEGRATED_LIGHTWEIGHT_FRAME"
ref_plane "工作平面15" through (0, 0, 261.5) normal (0, 0, 1) x (1, 0, 0) in component "07_GPU_INTEGRATED_LIGHTWEIGHT_FRAME"
sketch "草图15 (6)" plane through (0, 0, 261.5) normal (0, 0, 1) x (1, 0, 0) in component "07_GPU_INTEGRATED_LIGHTWEIGHT_FRAME"
  circle A0 centre (120, 251) radius 2.35
extrude "V20 unchanged upper ear short M3 heat insert (1)" cut sketch "草图15 (6)" along normal blind 6.5 bodies 33 in component "07_GPU_INTEGRATED_LIGHTWEIGHT_FRAME"
ref_plane "工作平面16" through (0, 0, 140) normal (0, 0, 1) x (1, 0, 0) in component "07_GPU_INTEGRATED_LIGHTWEIGHT_FRAME"
sketch "草图16 (5)" plane through (0, 0, 140) normal (0, 0, 1) x (1, 0, 0) in component "07_GPU_INTEGRATED_LIGHTWEIGHT_FRAME"
  line L0 (70, 264) -> (150, 264)
  line L1 (150, 264) -> (150, 272)
  line L2 (150, 272) -> (70, 272)
  line L3 (70, 272) -> (70, 264)
extrude "V20 continuous rear sole without intersecting corner notches" add sketch "草图16 (5)" along normal blind 8 bodies 33 in component "07_GPU_INTEGRATED_LIGHTWEIGHT_FRAME"
ref_plane "工作平面29" through (0, 0, 29.8) normal (0, 0, 1) x (1, 0, 0) in component "05_CENTERED_FLAT_PSU_CRADLE_OPEN_INTAKE"
sketch "草图29" plane through (0, 0, 29.8) normal (0, 0, 1) x (1, 0, 0) in component "05_CENTERED_FLAT_PSU_CRADLE_OPEN_INTAKE"
  line L0 (77.4, 47.52) -> (85.4, 47.52)
  line L1 (85.4, 47.52) -> (85.4, 51.52)
  line L2 (85.4, 51.52) -> (77.4, 51.52)
  line L3 (77.4, 51.52) -> (77.4, 47.52)
extrude "V22 front PSU end stop X77.4" add sketch "草图29" along normal blind 14.2 bodies 20 in component "05_CENTERED_FLAT_PSU_CRADLE_OPEN_INTAKE"
ref_plane "工作平面30" through (0, 0, 29.8) normal (0, 0, 1) x (1, 0, 0) in component "05_CENTERED_FLAT_PSU_CRADLE_OPEN_INTAKE"
sketch "草图30" plane through (0, 0, 29.8) normal (0, 0, 1) x (1, 0, 0) in component "05_CENTERED_FLAT_PSU_CRADLE_OPEN_INTAKE"
  line L0 (77.4, 192.32) -> (85.4, 192.32)
  line L1 (85.4, 192.32) -> (85.4, 196.32)
  line L2 (85.4, 196.32) -> (77.4, 196.32)
  line L3 (77.4, 196.32) -> (77.4, 192.32)
extrude "V22 rear PSU end stop X77.4" add sketch "草图30" along normal blind 14.2 bodies 20 in component "05_CENTERED_FLAT_PSU_CRADLE_OPEN_INTAKE"
ref_plane "工作平面31" through (77.4, 0, 0) normal (1, 0, 0) x (0, 1, 0) in component "05_CENTERED_FLAT_PSU_CRADLE_OPEN_INTAKE"
sketch "草图31" plane through (77.4, 0, 0) normal (1, 0, 0) x (0, 0, -1) in component "05_CENTERED_FLAT_PSU_CRADLE_OPEN_INTAKE"
  line L0 (-29.8, 45.52) -> (-29.8, 47.52)
  line L1 (-29.8, 47.52) -> (-44, 47.52)
  line L2 (-44, 47.52) -> (-29.8, 45.52)
extrude "V22 front stop outward gusset" add sketch "草图31" along normal blind 8 bodies 20 in component "05_CENTERED_FLAT_PSU_CRADLE_OPEN_INTAKE"
ref_plane "工作平面32" through (77.4, 0, 0) normal (1, 0, 0) x (0, 1, 0) in component "05_CENTERED_FLAT_PSU_CRADLE_OPEN_INTAKE"
sketch "草图32" plane through (77.4, 0, 0) normal (1, 0, 0) x (0, 0, -1) in component "05_CENTERED_FLAT_PSU_CRADLE_OPEN_INTAKE"
  line L0 (-29.8, 196.32) -> (-29.8, 198.32)
  line L1 (-29.8, 198.32) -> (-44, 196.32)
  line L2 (-44, 196.32) -> (-29.8, 196.32)
extrude "V22 rear stop outward gusset" add sketch "草图32" along normal blind 8 bodies 20 in component "05_CENTERED_FLAT_PSU_CRADLE_OPEN_INTAKE"
ref_plane "工作平面33" through (0, 0, 29.8) normal (0, 0, 1) x (1, 0, 0) in component "05_CENTERED_FLAT_PSU_CRADLE_OPEN_INTAKE"
sketch "草图33" plane through (0, 0, 29.8) normal (0, 0, 1) x (1, 0, 0) in component "05_CENTERED_FLAT_PSU_CRADLE_OPEN_INTAKE"
  line L0 (219.4, 47.52) -> (227.4, 47.52)
  line L1 (227.4, 47.52) -> (227.4, 51.52)
  line L2 (227.4, 51.52) -> (219.4, 51.52)
  line L3 (219.4, 51.52) -> (219.4, 47.52)
extrude "V22 front PSU end stop X219.4" add sketch "草图33" along normal blind 14.2 bodies 20 in component "05_CENTERED_FLAT_PSU_CRADLE_OPEN_INTAKE"
ref_plane "工作平面34" through (0, 0, 29.8) normal (0, 0, 1) x (1, 0, 0) in component "05_CENTERED_FLAT_PSU_CRADLE_OPEN_INTAKE"
sketch "草图34" plane through (0, 0, 29.8) normal (0, 0, 1) x (1, 0, 0) in component "05_CENTERED_FLAT_PSU_CRADLE_OPEN_INTAKE"
  line L0 (219.4, 192.32) -> (227.4, 192.32)
  line L1 (227.4, 192.32) -> (227.4, 196.32)
  line L2 (227.4, 196.32) -> (219.4, 196.32)
  line L3 (219.4, 196.32) -> (219.4, 192.32)
extrude "V22 rear PSU end stop X219.4" add sketch "草图34" along normal blind 14.2 bodies 20 in component "05_CENTERED_FLAT_PSU_CRADLE_OPEN_INTAKE"
ref_plane "工作平面35" through (219.4, 0, 0) normal (1, 0, 0) x (0, 1, 0) in component "05_CENTERED_FLAT_PSU_CRADLE_OPEN_INTAKE"
sketch "草图35" plane through (219.4, 0, 0) normal (1, 0, 0) x (0, 0, -1) in component "05_CENTERED_FLAT_PSU_CRADLE_OPEN_INTAKE"
  line L0 (-29.8, 45.52) -> (-29.8, 47.52)
  line L1 (-29.8, 47.52) -> (-44, 47.52)
  line L2 (-44, 47.52) -> (-29.8, 45.52)
extrude "V22 front stop outward gusset (1)" add sketch "草图35" along normal blind 8 bodies 20 in component "05_CENTERED_FLAT_PSU_CRADLE_OPEN_INTAKE"
ref_plane "工作平面36" through (219.4, 0, 0) normal (1, 0, 0) x (0, 1, 0) in component "05_CENTERED_FLAT_PSU_CRADLE_OPEN_INTAKE"
sketch "草图36" plane through (219.4, 0, 0) normal (1, 0, 0) x (0, 0, -1) in component "05_CENTERED_FLAT_PSU_CRADLE_OPEN_INTAKE"
  line L0 (-29.8, 196.32) -> (-29.8, 198.32)
  line L1 (-29.8, 198.32) -> (-44, 196.32)
  line L2 (-44, 196.32) -> (-29.8, 196.32)
extrude "V22 rear stop outward gusset (1)" add sketch "草图36" along normal blind 8 bodies 20 in component "05_CENTERED_FLAT_PSU_CRADLE_OPEN_INTAKE"
ref_plane "工作平面11" through (0, 25.01, 0) normal (0, 1, 0) x (0, 0, 1) in component "10_GPU_140_FAN_MOUNT"
sketch "草图11 (14)" plane through (0, 25.01, 0) normal (0, 1, 0) x (1, 0, 0) in component "10_GPU_140_FAN_MOUNT"
  circle A0 through (22.65, -217.5, -50.02) (18.525, -215.1184, -50.02) (18.525, -219.8816, -50.02)
extrude "V23 125 pitch D5.5 clearance for fan self tapping screw" cut sketch "草图11 (14)" along normal blind 6.02 contours A0 in plane through (0, -25.01, 0) normal (0, 1, 0) bodies 1 in component "10_GPU_140_FAN_MOUNT"
ref_plane "工作平面12" through (0, 22, 0) normal (0, 1, 0) x (0, 0, 1) in component "10_GPU_140_FAN_MOUNT"
sketch "草图12 (10)" plane through (0, 22, 0) normal (0, 1, 0) x (1, 0, 0) in component "10_GPU_140_FAN_MOUNT"
  circle A0 through (23.4, -217.5, -44) (18.15, -214.4689, -44) (18.15, -220.5311, -44)
extrude "V23 rear D7 counterbore leaves 3mm bearing web" cut sketch "草图12 (10)" along normal blind 3.01 contours A0 in plane through (0, -22, 0) normal (0, 1, 0) bodies 1 in component "10_GPU_140_FAN_MOUNT"
ref_plane "工作平面13" through (0, 25.01, 0) normal (0, 1, 0) x (0, 0, 1) in component "10_GPU_140_FAN_MOUNT"
sketch "草图13 (9)" plane through (0, 25.01, 0) normal (0, 1, 0) x (1, 0, 0) in component "10_GPU_140_FAN_MOUNT"
  circle A0 through (22.65, -342.5, -50.02) (18.525, -340.1184, -50.02) (18.525, -344.8816, -50.02)
extrude "V23 125 pitch D5.5 clearance for fan self tapping screw (1)" cut sketch "草图13 (9)" along normal blind 6.02 contours A0 in plane through (0, -25.01, 0) normal (0, 1, 0) bodies 1 in component "10_GPU_140_FAN_MOUNT"
ref_plane "工作平面14" through (0, 22, 0) normal (0, 1, 0) x (0, 0, 1) in component "10_GPU_140_FAN_MOUNT"
sketch "草图14 (9)" plane through (0, 22, 0) normal (0, 1, 0) x (1, 0, 0) in component "10_GPU_140_FAN_MOUNT"
  circle A0 through (23.4, -342.5, -44) (18.15, -339.4689, -44) (18.15, -345.5311, -44)
extrude "V23 rear D7 counterbore leaves 3mm bearing web (1)" cut sketch "草图14 (9)" along normal blind 3.01 contours A0 in plane through (0, -22, 0) normal (0, 1, 0) bodies 1 in component "10_GPU_140_FAN_MOUNT"
ref_plane "工作平面15" through (0, 25.01, 0) normal (0, 1, 0) x (0, 0, 1) in component "10_GPU_140_FAN_MOUNT"
sketch "草图15 (7)" plane through (0, 25.01, 0) normal (0, 1, 0) x (1, 0, 0) in component "10_GPU_140_FAN_MOUNT"
  circle A0 through (147.65, -217.5, -50.02) (143.525, -215.1184, -50.02) (143.525, -219.8816, -50.02)
extrude "V23 125 pitch D5.5 clearance for fan self tapping screw (2)" cut sketch "草图15 (7)" along normal blind 6.02 contours A0 in plane through (0, -25.01, 0) normal (0, 1, 0) bodies 1 in component "10_GPU_140_FAN_MOUNT"
ref_plane "工作平面16" through (0, 22, 0) normal (0, 1, 0) x (0, 0, 1) in component "10_GPU_140_FAN_MOUNT"
sketch "草图16 (6)" plane through (0, 22, 0) normal (0, 1, 0) x (1, 0, 0) in component "10_GPU_140_FAN_MOUNT"
  circle A0 through (148.4, -217.5, -44) (143.15, -214.4689, -44) (143.15, -220.5311, -44)
extrude "V23 rear D7 counterbore leaves 3mm bearing web (2)" cut sketch "草图16 (6)" along normal blind 3.01 contours A0 in plane through (0, -22, 0) normal (0, 1, 0) bodies 1 in component "10_GPU_140_FAN_MOUNT"
ref_plane "工作平面17" through (0, 25.01, 0) normal (0, 1, 0) x (0, 0, 1) in component "10_GPU_140_FAN_MOUNT"
sketch "草图17 (4)" plane through (0, 25.01, 0) normal (0, 1, 0) x (1, 0, 0) in component "10_GPU_140_FAN_MOUNT"
  circle A0 through (147.65, -342.5, -50.02) (143.525, -340.1184, -50.02) (143.525, -344.8816, -50.02)
extrude "V23 125 pitch D5.5 clearance for fan self tapping screw (3)" cut sketch "草图17 (4)" along normal blind 6.02 contours A0 in plane through (0, -25.01, 0) normal (0, 1, 0) bodies 1 in component "10_GPU_140_FAN_MOUNT"
ref_plane "工作平面18" through (0, 22, 0) normal (0, 1, 0) x (0, 0, 1) in component "10_GPU_140_FAN_MOUNT"
sketch "草图18 (3)" plane through (0, 22, 0) normal (0, 1, 0) x (1, 0, 0) in component "10_GPU_140_FAN_MOUNT"
  circle A0 through (148.4, -342.5, -44) (143.15, -339.4689, -44) (143.15, -345.5311, -44)
extrude "V23 rear D7 counterbore leaves 3mm bearing web (3)" cut sketch "草图18 (3)" along normal blind 3.01 contours A0 in plane through (0, -22, 0) normal (0, 1, 0) bodies 1 in component "10_GPU_140_FAN_MOUNT"
ref_plane "工作平面11" through (0, 25.01, 0) normal (0, 1, 0) x (0, 0, 1) in component "10_CPU_140_FAN_MOUNT"
sketch "草图11 (15)" plane through (0, 25.01, 0) normal (0, 1, 0) x (1, 0, 0) in component "10_CPU_140_FAN_MOUNT"
  circle A0 through (166.65, -217.5, -50.02) (162.525, -215.1184, -50.02) (162.525, -219.8816, -50.02)
extrude "V23 125 pitch D5.5 clearance for fan self tapping screw'" cut sketch "草图11 (15)" along normal blind 6.02 contours A0 in plane through (0, -25.01, 0) normal (0, 1, 0) bodies 2 in component "10_CPU_140_FAN_MOUNT"
ref_plane "工作平面12" through (0, 22, 0) normal (0, 1, 0) x (0, 0, 1) in component "10_CPU_140_FAN_MOUNT"
sketch "草图12 (11)" plane through (0, 22, 0) normal (0, 1, 0) x (1, 0, 0) in component "10_CPU_140_FAN_MOUNT"
  circle A0 through (167.4, -217.5, -44) (162.15, -214.4689, -44) (162.15, -220.5311, -44)
extrude "V23 rear D7 counterbore leaves 3mm bearing web'" cut sketch "草图12 (11)" along normal blind 3.01 contours A0 in plane through (0, -22, 0) normal (0, 1, 0) bodies 2 in component "10_CPU_140_FAN_MOUNT"
ref_plane "工作平面13" through (0, 25.01, 0) normal (0, 1, 0) x (0, 0, 1) in component "10_CPU_140_FAN_MOUNT"
sketch "草图13 (10)" plane through (0, 25.01, 0) normal (0, 1, 0) x (1, 0, 0) in component "10_CPU_140_FAN_MOUNT"
  circle A0 through (166.65, -342.5, -50.02) (162.525, -340.1184, -50.02) (162.525, -344.8816, -50.02)
extrude "V23 125 pitch D5.5 clearance for fan self tapping screw (1)'" cut sketch "草图13 (10)" along normal blind 6.02 contours A0 in plane through (0, -25.01, 0) normal (0, 1, 0) bodies 2 in component "10_CPU_140_FAN_MOUNT"
ref_plane "工作平面14" through (0, 22, 0) normal (0, 1, 0) x (0, 0, 1) in component "10_CPU_140_FAN_MOUNT"
sketch "草图14 (10)" plane through (0, 22, 0) normal (0, 1, 0) x (1, 0, 0) in component "10_CPU_140_FAN_MOUNT"
  circle A0 through (167.4, -342.5, -44) (162.15, -339.4689, -44) (162.15, -345.5311, -44)
extrude "V23 rear D7 counterbore leaves 3mm bearing web (1)'" cut sketch "草图14 (10)" along normal blind 3.01 contours A0 in plane through (0, -22, 0) normal (0, 1, 0) bodies 2 in component "10_CPU_140_FAN_MOUNT"
ref_plane "工作平面15" through (0, 25.01, 0) normal (0, 1, 0) x (0, 0, 1) in component "10_CPU_140_FAN_MOUNT"
sketch "草图15 (8)" plane through (0, 25.01, 0) normal (0, 1, 0) x (1, 0, 0) in component "10_CPU_140_FAN_MOUNT"
  circle A0 through (291.65, -217.5, -50.02) (287.525, -215.1184, -50.02) (287.525, -219.8816, -50.02)
extrude "V23 125 pitch D5.5 clearance for fan self tapping screw (2)'" cut sketch "草图15 (8)" along normal blind 6.02 contours A0 in plane through (0, -25.01, 0) normal (0, 1, 0) bodies 2 in component "10_CPU_140_FAN_MOUNT"
ref_plane "工作平面16" through (0, 22, 0) normal (0, 1, 0) x (0, 0, 1) in component "10_CPU_140_FAN_MOUNT"
sketch "草图16 (7)" plane through (0, 22, 0) normal (0, 1, 0) x (1, 0, 0) in component "10_CPU_140_FAN_MOUNT"
  circle A0 through (292.4, -217.5, -44) (287.15, -214.4689, -44) (287.15, -220.5311, -44)
extrude "V23 rear D7 counterbore leaves 3mm bearing web (2)'" cut sketch "草图16 (7)" along normal blind 3.01 contours A0 in plane through (0, -22, 0) normal (0, 1, 0) bodies 2 in component "10_CPU_140_FAN_MOUNT"
ref_plane "工作平面17" through (0, 25.01, 0) normal (0, 1, 0) x (0, 0, 1) in component "10_CPU_140_FAN_MOUNT"
sketch "草图17 (5)" plane through (0, 25.01, 0) normal (0, 1, 0) x (1, 0, 0) in component "10_CPU_140_FAN_MOUNT"
  circle A0 through (291.65, -342.5, -50.02) (287.525, -340.1184, -50.02) (287.525, -344.8816, -50.02)
extrude "V23 125 pitch D5.5 clearance for fan self tapping screw (3)'" cut sketch "草图17 (5)" along normal blind 6.02 contours A0 in plane through (0, -25.01, 0) normal (0, 1, 0) bodies 2 in component "10_CPU_140_FAN_MOUNT"
ref_plane "工作平面18" through (0, 22, 0) normal (0, 1, 0) x (0, 0, 1) in component "10_CPU_140_FAN_MOUNT"
sketch "草图18 (4)" plane through (0, 22, 0) normal (0, 1, 0) x (1, 0, 0) in component "10_CPU_140_FAN_MOUNT"
  circle A0 through (292.4, -342.5, -44) (287.15, -339.4689, -44) (287.15, -345.5311, -44)
extrude "V23 rear D7 counterbore leaves 3mm bearing web (3)'" cut sketch "草图18 (4)" along normal blind 3.01 contours A0 in plane through (0, -22, 0) normal (0, 1, 0) bodies 2 in component "10_CPU_140_FAN_MOUNT"
ref_plane "工作平面37" through (0, 0, 11) normal (0, 0, 1) x (1, 0, 0) in component "05_CENTERED_FLAT_PSU_CRADLE_OPEN_INTAKE"
sketch "草图37" plane through (0, 0, 11) normal (0, 0, 1) x (1, 0, 0) in component "05_CENTERED_FLAT_PSU_CRADLE_OPEN_INTAKE"
  circle A0 centre (225.4, 203.92) radius 4.1
extrude "V24 M3x6 D7 head well D8.2 compensated" cut sketch "草图37" along normal blind 19.02 bodies 20 in component "05_CENTERED_FLAT_PSU_CRADLE_OPEN_INTAKE"
ref_plane "工作平面38" through (0, 0, 11) normal (0, 0, 1) x (1, 0, 0) in component "05_CENTERED_FLAT_PSU_CRADLE_OPEN_INTAKE"
sketch "草图38" plane through (0, 0, 11) normal (0, 0, 1) x (1, 0, 0) in component "05_CENTERED_FLAT_PSU_CRADLE_OPEN_INTAKE"
  circle A0 centre (79.4, 203.92) radius 4.1
extrude "V24 M3x6 D7 head well D8.2 compensated (1)" cut sketch "草图38" along normal blind 19.02 bodies 20 in component "05_CENTERED_FLAT_PSU_CRADLE_OPEN_INTAKE"
ref_plane "工作平面39" through (0, 0, 11) normal (0, 0, 1) x (1, 0, 0) in component "05_CENTERED_FLAT_PSU_CRADLE_OPEN_INTAKE"
sketch "草图39" plane through (0, 0, 11) normal (0, 0, 1) x (1, 0, 0) in component "05_CENTERED_FLAT_PSU_CRADLE_OPEN_INTAKE"
  circle A0 centre (225.4, 39.92) radius 4.1
extrude "V24 M3x6 D7 head well D8.2 compensated (2)" cut sketch "草图39" along normal blind 19.02 bodies 20 in component "05_CENTERED_FLAT_PSU_CRADLE_OPEN_INTAKE"
ref_plane "工作平面40" through (0, 0, 11) normal (0, 0, 1) x (1, 0, 0) in component "05_CENTERED_FLAT_PSU_CRADLE_OPEN_INTAKE"
sketch "草图40" plane through (0, 0, 11) normal (0, 0, 1) x (1, 0, 0) in component "05_CENTERED_FLAT_PSU_CRADLE_OPEN_INTAKE"
  circle A0 centre (79.4, 39.92) radius 4.1
extrude "V24 M3x6 D7 head well D8.2 compensated (3)" cut sketch "草图40" along normal blind 19.02 bodies 20 in component "05_CENTERED_FLAT_PSU_CRADLE_OPEN_INTAKE"
ref_plane "工作平面15" through (0, 10, 0) normal (0, 1, 0) x (0, 0, 1) in component "12_front_PCI_SUPPORT_FRAME"
sketch "草图15 (9)" plane through (0, 10, 0) normal (0, 1, 0) x (1, 0, 0) in component "12_front_PCI_SUPPORT_FRAME"
  circle A0 through (9.04, -132, -20) (2.89, -128.4493, -20) (2.89, -135.5507, -20)
extrude "V24 M3x6 D7 head well D8.2 compensated'" cut sketch "草图15 (9)" along normal blind 13.02 contours A0 in plane through (0, -10, 0) normal (0, 1, 0) bodies 24 in component "12_front_PCI_SUPPORT_FRAME"
ref_plane "工作平面16" through (0, 10, 0) normal (0, 1, 0) x (0, 0, 1) in component "12_front_PCI_SUPPORT_FRAME"
sketch "草图16 (8)" plane through (0, 10, 0) normal (0, 1, 0) x (1, 0, 0) in component "12_front_PCI_SUPPORT_FRAME"
  circle A0 through (23.61, -8, -20) (17.46, -4.4493, -20) (17.46, -11.5507, -20)
extrude "V24 M3x6 D7 head well D8.2 compensated (1)'" cut sketch "草图16 (8)" along normal blind 13.02 contours A0 in plane through (0, -10, 0) normal (0, 1, 0) bodies 24 in component "12_front_PCI_SUPPORT_FRAME"
ref_plane "工作平面16" through (0, 10, 0) normal (0, 1, 0) x (0, 0, 1) in component "12_front_CPU_SUPPORT_FRAME"